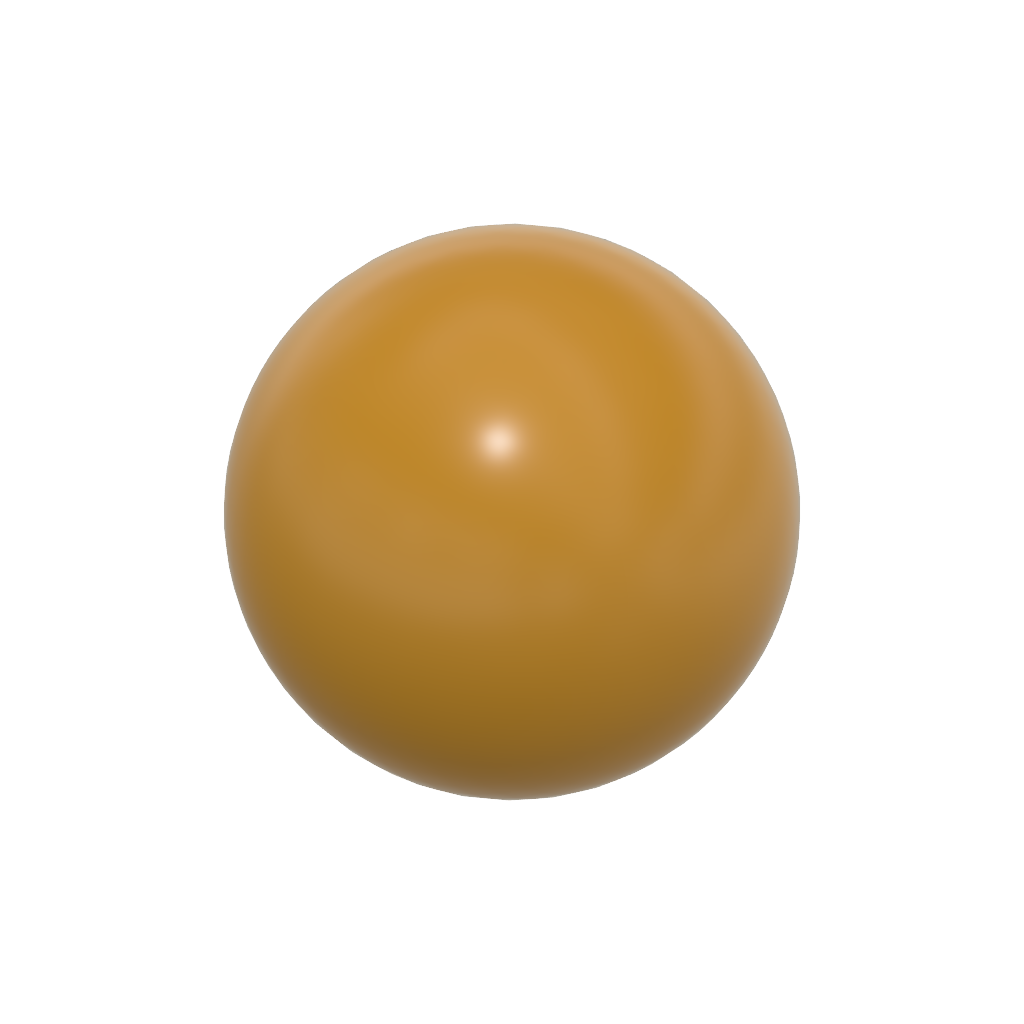
Assembly (Autodesk Fusion 360 archive; units mm, degrees)
design "Ping Pong Ball"
part number: 2026-09-19-06-45-59-670
Autodesk Fusion 360 part; units mm, degrees
sketch "草图1" plane through (0, 0, 0) normal (1, 0, 0) x (0, 0, -1)
  line L0 (0, 20) -> (0, -20)
  arc A0 (0, -20) -> (0, 20) centre (0, 0) ccw
  dimension "d1" = 40
  constraint coincident A0.centre origin
  constraint perpendicular L0 A0
  measures "d1" diameter of A0
revolve "旋转1" add sketch "草图1" angle 360 about axis through (0, 20, 0) along (0, -1, 0)

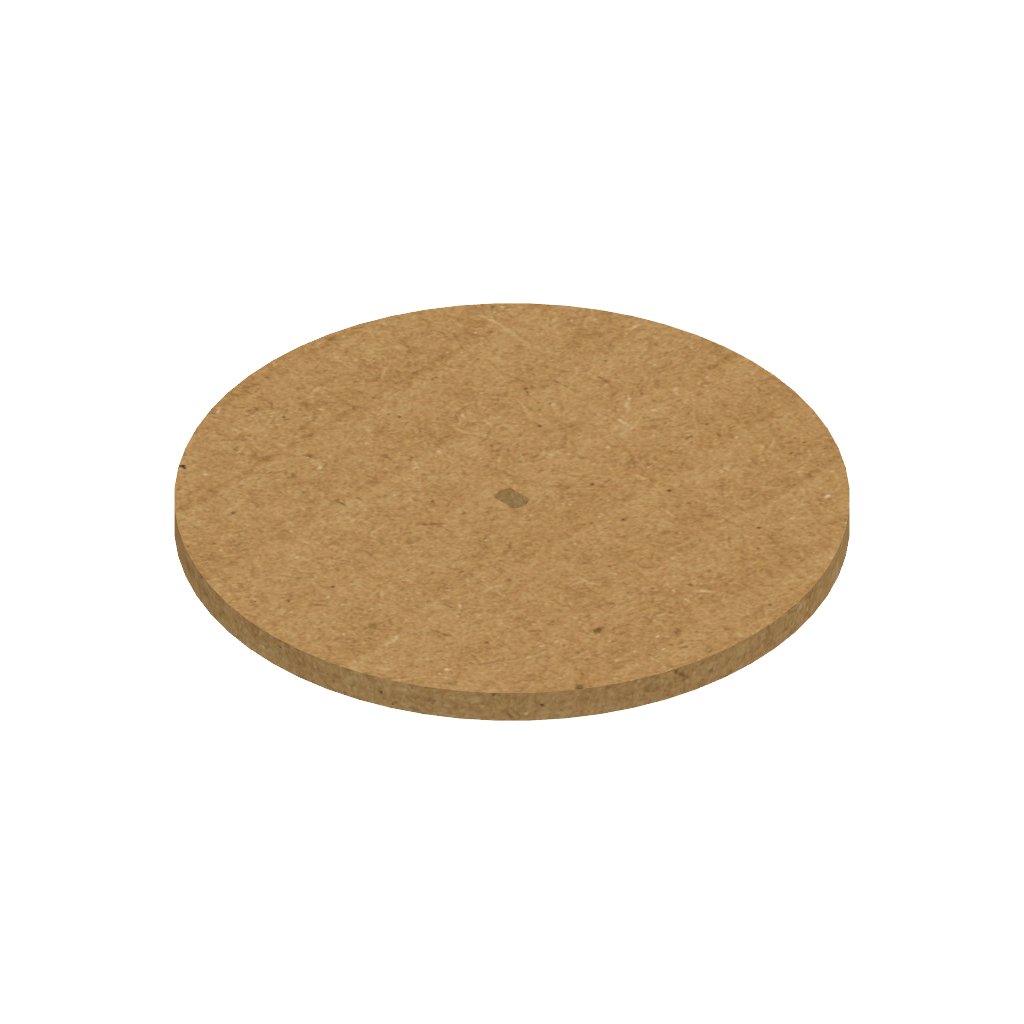
design "Wheel_Cardboard"
part number: 2026-09-13-15-54-39-703
Autodesk Fusion 360 part; units mm, degrees
sketch "Sketch1" plane through (0, 0, 0) normal (0, 1, 0) x (1, 0, 0)
  circle A0 centre (0, 0) radius 50
  line L0 (-1.972, 1.725) -> (1.972, 1.725)
  line L1 (-1.972, -1.725) -> (1.972, -1.725)
  line L2 (-50, 0) -> (50, 0) construction
  arc A1 (-1.972, 1.725) -> (-1.972, -1.725) centre (0, 0) ccw
  arc A2 (1.972, -1.725) -> (1.972, 1.725) centre (0, 0) ccw
  dimension "d1" = 2.62
  dimension "d2" = 3.45
  dimension "d3" = 100
  constraint coincident A0.centre A1.centre
  constraint concentric A0 A1
  constraint horizontal L0
  constraint parallel L0 L1
  constraint coincident A0 L2.start
  constraint coincident A0 L2.end
  constraint perpendicular A0 L2
  constraint concentric A1 A2
  constraint symmetric L0 L1 L2
  constraint equal A1 A2
  measures "d1" radius of A2
  measures "d2" distance of L0 L1
  measures "d3" diameter of A0
extrude "拉伸1" add sketch "Sketch1" along normal blind 5

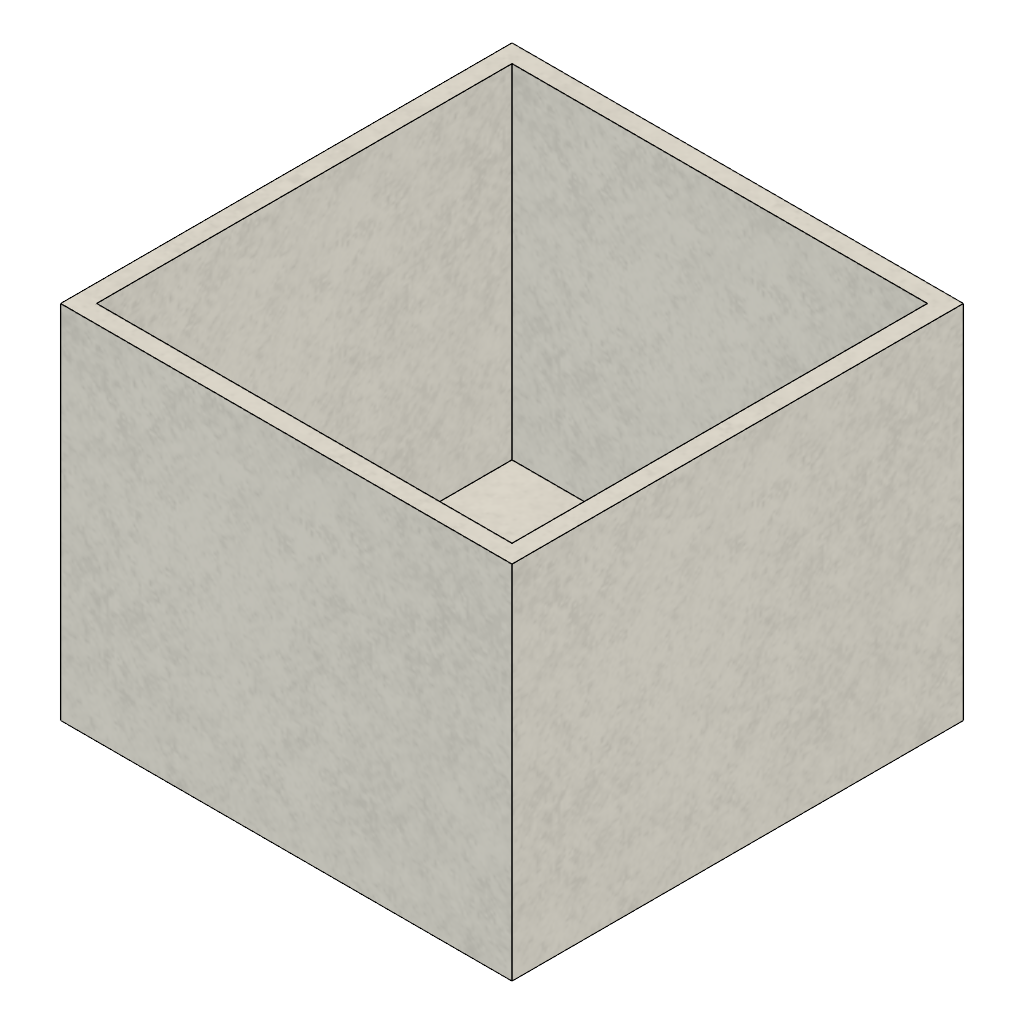
design "Ball Basket"
part number: 2026-09-14-14-18-43-372
Autodesk Fusion 360 part; units mm, degrees
sketch "草图1" plane through (0, 0, 0) normal (0, 1, 0) x (1, 0, 0)
  line L0 (0, 0) -> (50, 0)
  line L1 (50, 0) -> (50, -50)
  line L2 (50, -50) -> (0, -50)
  line L3 (0, -50) -> (0, 0)
  line L4 (2, -48) -> (2, -2)
  line L5 (2, -2) -> (48, -2)
  line L6 (48, -2) -> (48, -48)
  line L7 (48, -48) -> (2, -48)
  dimension "d2" = 50
  dimension "d3" = 2
  constraint horizontal L0
  constraint vertical L1
  constraint horizontal L2
  constraint vertical L3
  constraint coincident L0.start L3.end
  constraint equal L0 L3
  measures "d2" distance of L0.start L2.end
extrude "拉伸1" add sketch "草图1" along normal blind 2 contours L4 L5 L6 L7 makes body 1
extrude "拉伸3" add sketch "草图1" along normal blind 40 separate body makes body 2

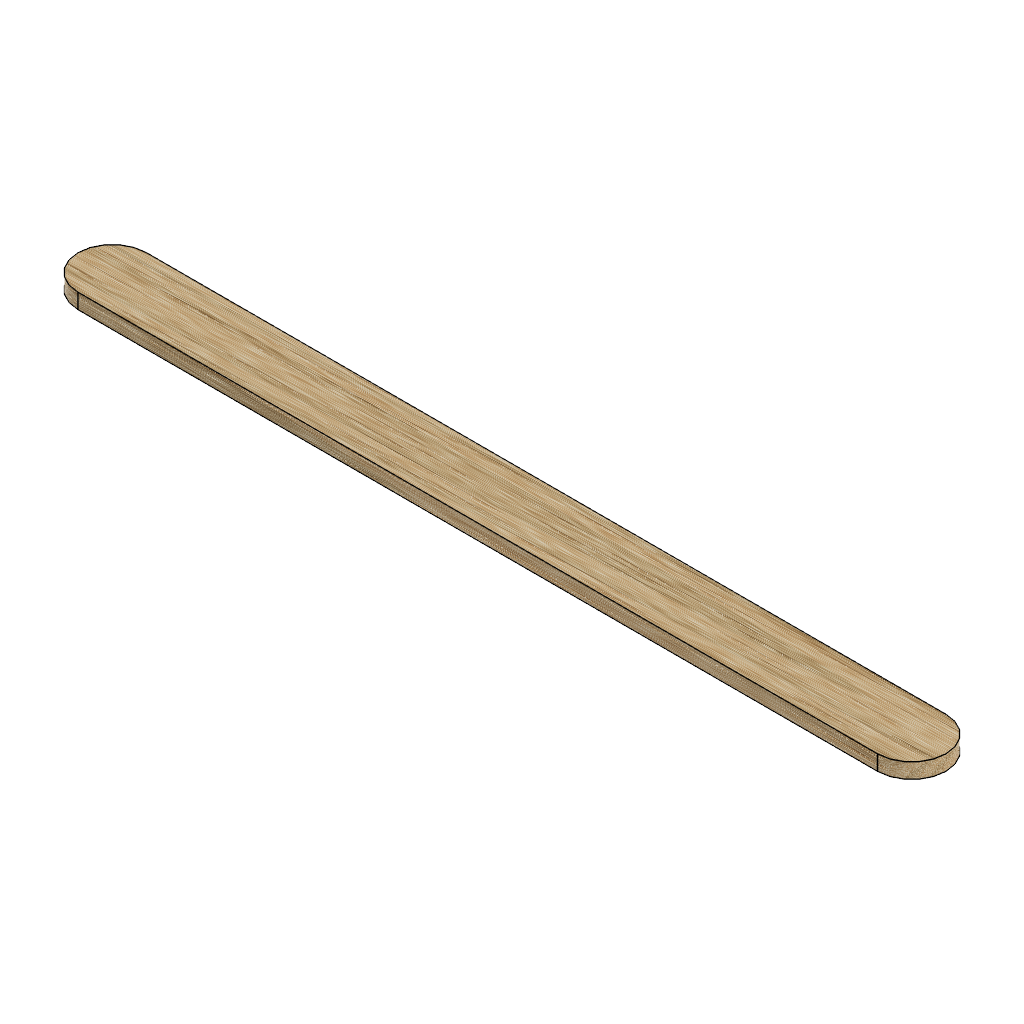
design "Stick"
Autodesk Fusion 360 part; units mm, degrees
sketch "Sketch1" plane through (0, 0, 0) normal (0, 0, 1) x (1, 0, 0)
  line L0 (52.5, -4.5) -> (-52.5, -4.5)
  line L1 (-52.5, 4.5) -> (52.5, 4.5)
  line L2 (52.5, -4.5) -> (-52.5, 4.5) construction
  line L3 (-52.5, -4.5) -> (52.5, 4.5) construction
  arc A0 (-52.5, 4.5) -> (-52.5, -4.5) centre (-52.5, 0) ccw
  arc A1 (52.5, -4.5) -> (51.7342, 4.4344) centre (52.5, 0) ccw
  dimension "d9" = 105
  dimension "d10" = 9
  constraint horizontal L0
  constraint parallel L0 L1
  constraint coincident L2 origin
  constraint coincident L3 origin
  constraint coincident L1.end A1
  constraint coincident L1.start A0
  constraint coincident L3 L0.end
  constraint coincident L2 L1.start
  constraint coincident L3 A1.end
  constraint coincident L2 L0.start
  constraint tangent L1 A1
  constraint tangent L0 A1
  constraint tangent L0 A0
  constraint tangent L1 A0
  constraint coincident L0.start L2.start
  constraint coincident L0.end L3.start
  measures "d9" distance of L1.start L1.end
  measures "d10" distance of L0.end L1.start
extrude "Extrude1" add sketch "Sketch1" along normal blind 2
